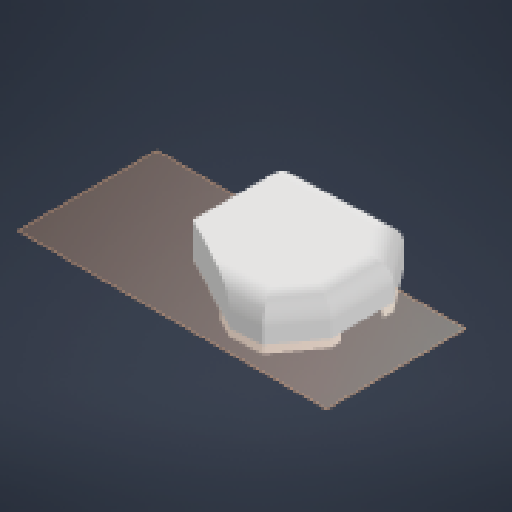
# Autodesk Inventor part: case1
Saved by Autodesk Inventor 2026.2 (Build 302298000, 298)
## iProperties
Created: 2026-10-14
Part Number: case1
Material: Generisch
Document SubType Name: Modeling
Designer: leo
Density: 1 g/cm^3
Appearance: Vorgabe
Author: leo
Autodesk Inventor part; units mm, degrees
ref_plane "YZ Plane" through (0, 0, 0) normal (1, 0, 0) x (0, 1, 0)
ref_plane "XZ Plane" through (0, 0, 0) normal (0, 1, 0) x (-1, 0, 0)
ref_plane "XY Plane" through (0, 0, 0) normal (0, 0, 1) x (1, 0, 0)
ref_plane "Arbeitsebene1" through (0, 0, 0) normal (0, 0, 1) x (1, 0, 0)
sketch "Skizze1" plane through (0, 0, 0) normal (0, 0, 1) x (1, 0, 0)
  line L0 (29.7049, 7.294) -> (29.7049, 3.444) projected
  line L1 (26.9489, 8.327) -> (29.7049, 7.294) projected
  line L2 (20.6569, 8.733) -> (26.9489, 8.327) projected
  line L3 (14.3239, 13.04) -> (20.6569, 8.733) projected
  line L4 (-6.9251, 12.08) -> (14.3239, 13.04) projected
  line L5 (-6.9251, -1.131) -> (-6.9251, 12.08) projected
  line L6 (-26.1451, -1.131) -> (-6.9251, -1.131) projected
  line L7 (-26.8451, -6.991) -> (-26.1451, -1.131) projected
  line L8 (-26.1151, -12.431) -> (-26.8451, -6.991) projected
  line L9 (0.5049, -12.431) -> (-26.1151, -12.431) projected
  line L10 (3.9049, -9.031) -> (0.5049, -12.431) projected
  line L11 (3.9049, -5.536) -> (3.9049, -9.031) projected
  line L12 (8.5589, -2.362) -> (3.9049, -5.536) projected
  line L13 (14.8709, -1.962) -> (8.5589, -2.362) projected
  line L14 (20.7089, 2.008) -> (14.8709, -1.962) projected
  line L15 (26.9489, 2.411) -> (20.7089, 2.008) projected
  line L16 (29.7049, 3.444) -> (26.9489, 2.411) projected
  circle A0 centre (4.6149, -2.071) radius 1.35 projected
  circle A1 centre (1.4409, 9.847) radius 1 projected
  circle A2 centre (1.4409, 3.347) radius 1 projected
  circle A3 centre (-5.0591, 3.347) radius 1 projected
  circle A4 centre (-1.8091, 6.597) radius 0.65 projected
  circle A5 centre (-5.0591, 9.847) radius 1 projected
  line L17 (-6.9251, 19.0871) -> (14.3239, 20.0471)
  line L18 (14.3239, 20.0471) -> (20.6569, 11.733)
  line L19 (20.7089, -0.992) -> (14.8709, -8.962)
  line L20 (20.7089, -0.992) -> (20.6569, 11.733)
  line L21 (14.8709, -8.962) -> (8.5589, -9.362)
  line L22 (-6.9251, 19.0871) -> (-6.9251, -1.131)
  line L23 (8.5589, -9.362) -> (-6.9251, -1.131)
  point P0 (0, 0)
  point P1 (20.6691, 8.7322)
  dimension "d0" = 7
  dimension "d1" = 3
  dimension "d2" = 3
  dimension "d3" = 7
  constraints: 14 end point, 6 vertical alignment, 2 parallel, 1 vertical
  measures "d0" distance between parallel lines of L4 L17
  measures "d1" distance of L2.start L18.end
  measures "d2" distance of L14.start L19.start
  measures "d3" distance of L13.start L19.end
extrude "Extrusion1" add sketch "Skizze1" along normal blind 7 contours L20 L14 L13 L12 L11 L23 L5 L4 L3 L2 | L2 L3 L4 L22 L17 L18 L20 | L20 L19 L21 L23 L11 L12 L13 L14 | A0 | A1 | A2 | A3 | A4 | A5
sketch "Skizze2" plane through (0, 0, 0) normal (0, 0, -1) x (-1, 0, 0)
  line L0 (-29.7049, 7.294) -> (-29.7049, 3.444) projected
  line L1 (-29.7049, 3.444) -> (-26.9489, 2.411) projected
  line L2 (-26.9489, 2.411) -> (-20.7089, 2.008) projected
  line L3 (-20.7089, 2.008) -> (-14.8709, -1.962) projected
  line L4 (-14.8709, -1.962) -> (-8.5589, -2.362) projected
  line L5 (-8.5589, -2.362) -> (-3.9049, -5.536) projected
  line L6 (-3.9049, -5.536) -> (-3.9049, -9.031) projected
  line L7 (-3.9049, -9.031) -> (-0.5049, -12.431) projected
  line L8 (-0.5049, -12.431) -> (26.1151, -12.431) projected
  line L9 (26.1151, -12.431) -> (26.8451, -6.991) projected
  line L10 (26.8451, -6.991) -> (26.1451, -1.131) projected
  line L11 (26.1451, -1.131) -> (6.9251, -1.131) projected
  line L12 (6.9251, -1.131) -> (6.9251, 12.08) projected
  line L13 (6.9251, 12.08) -> (-14.3239, 13.04) projected
  line L14 (-14.3239, 13.04) -> (-20.6569, 8.733) projected
  line L15 (-20.6569, 8.733) -> (-26.9489, 8.327) projected
  line L16 (-26.9489, 8.327) -> (-29.7049, 7.294) projected
  circle A0 centre (-4.6149, -2.071) radius 1.35 projected
  circle A1 centre (-1.4409, 9.847) radius 1 projected
  circle A2 centre (-1.4409, 3.347) radius 1 projected
  circle A3 centre (5.0591, 3.347) radius 1 projected
  circle A4 centre (1.8091, 6.597) radius 0.65 projected
  circle A5 centre (5.0591, 9.847) radius 1 projected
  circle A6 centre (-4.6149, -2.071) radius 2
  circle A7 centre (-1.4409, 9.847) radius 1.5
  circle A8 centre (5.0591, 9.847) radius 1.5
  circle A9 centre (1.8091, 6.597) radius 1
  circle A10 centre (-1.4409, 3.347) radius 1.5
  circle A11 centre (5.0591, 3.347) radius 1.5
  point P0 (0, 0)
  dimension "d6" = 4
  dimension "d7" = 3
  dimension "d8" = 3
  dimension "d9" = 2
  dimension "d10" = 3
  dimension "d11" = 3
  constraints: 6 centre point, 6 coincident
  measures "d6" diameter of A6
  measures "d7" diameter of A7
  measures "d8" diameter of A8
  measures "d9" diameter of A9
  measures "d10" diameter of A10
  measures "d11" diameter of A11
extrude "Extrusion2" cut sketch "Skizze2" against normal blind 4 contours A0 | A1 | A2 | A3 | A4 | A5 | A6 | A7 | A8 | A9 | A10 | A11
sketch "Skizze3" plane through (0, 0, 0) normal (0, 0, -1) x (-1, 0, 0)
  line L0 (-29.7049, 7.294) -> (-29.7049, 3.444) projected
  line L1 (-29.7049, 3.444) -> (-26.9489, 2.411) projected
  line L2 (-26.9489, 2.411) -> (-20.7089, 2.008) projected
  line L3 (-20.7089, 2.008) -> (-14.8709, -1.962) projected
  line L4 (-14.8709, -1.962) -> (-8.5589, -2.362) projected
  line L5 (-8.5589, -2.362) -> (-3.9049, -5.536) projected
  line L6 (-3.9049, -5.536) -> (-3.9049, -9.031) projected
  line L7 (-3.9049, -9.031) -> (-0.5049, -12.431) projected
  line L8 (-0.5049, -12.431) -> (26.1151, -12.431) projected
  line L9 (26.1151, -12.431) -> (26.8451, -6.991) projected
  line L10 (26.8451, -6.991) -> (26.1451, -1.131) projected
  line L11 (26.1451, -1.131) -> (6.9251, -1.131) projected
  line L12 (6.9251, -1.131) -> (6.9251, 12.08) projected
  line L13 (6.9251, 12.08) -> (-14.3239, 13.04) projected
  line L14 (-14.3239, 13.04) -> (-20.6569, 8.733) projected
  line L15 (-20.6569, 8.733) -> (-26.9489, 8.327) projected
  line L16 (-26.9489, 8.327) -> (-29.7049, 7.294) projected
  circle A0 centre (-4.6149, -2.071) radius 1.35 projected
  circle A1 centre (-1.4409, 9.847) radius 1 projected
  circle A2 centre (-1.4409, 3.347) radius 1 projected
  circle A3 centre (5.0591, 3.347) radius 1 projected
  circle A4 centre (1.8091, 6.597) radius 0.65 projected
  circle A5 centre (5.0591, 9.847) radius 1 projected
  line L17 (-14.5249, 13.7498) -> (7.6251, 12.7491)
  line L18 (7.6251, 12.7491) -> (7.6251, -0.431)
  line L19 (7.6251, -0.431) -> (26.7665, -0.431)
  line L20 (26.7665, -0.431) -> (27.5507, -6.9961)
  line L21 (27.5507, -6.9961) -> (26.7275, -13.131)
  line L22 (26.7275, -13.131) -> (-0.7948, -13.131)
  line L23 (-0.7948, -13.131) -> (-4.6049, -9.321)
  line L24 (-4.6049, -9.321) -> (-4.6049, -5.9059)
  line L25 (-4.6049, -5.9059) -> (-8.7947, -3.0485)
  line L26 (-8.7947, -3.0485) -> (-15.1062, -2.6485)
  line L27 (-15.1062, -2.6485) -> (-20.9446, 1.3217)
  line L28 (-20.9446, 1.3217) -> (-27.0974, 1.7191)
  line L29 (-27.0974, 1.7191) -> (-30.4049, 2.9588)
  line L30 (-30.4049, 2.9588) -> (-30.4049, 7.7792)
  line L31 (-30.4049, 7.7792) -> (-27.0974, 9.0188)
  line L32 (-27.0974, 9.0188) -> (-20.8925, 9.4192)
  line L33 (-20.8925, 9.4192) -> (-14.5249, 13.7498)
  circle A6 centre (5.0591, 3.347) radius 1.5 projected
  circle A7 centre (-1.4409, 9.847) radius 1.5 projected
  circle A8 centre (-1.4409, 3.347) radius 1.5 projected
  circle A9 centre (5.0591, 9.847) radius 1.5 projected
  circle A10 centre (1.8091, 6.597) radius 1 projected
  circle A11 centre (-4.6149, -2.071) radius 2 projected
  line L34 (6.9251, 19.0871) -> (6.9251, -1.131) projected
  line L35 (-14.3239, 20.0471) -> (6.9251, 19.0871) projected
  line L36 (-20.6569, 11.733) -> (-14.3239, 20.0471) projected
  line L37 (-20.7089, -0.992) -> (-20.6569, 11.733) projected
  line L38 (-14.8709, -8.962) -> (-20.7089, -0.992) projected
  line L39 (-8.5589, -9.362) -> (-14.8709, -8.962) projected
  line L40 (6.9251, -1.131) -> (-8.5589, -9.362) projected
  point P0 (0, 0)
  point P1 (-20.7001, 1.1555)
  point P2 (-4.6049, -7.2602)
  point P3 (-20.6657, 9.5735)
  point P4 (6.9251, 12.7807)
  dimension "d14" = 0.7
  constraints: 34 end point, 16 other
  measures "d14" distance between parallel lines of L13 L17
extrude "Extrusion3" add sketch "Skizze3" along normal blind 1.6 contours L37 L36 L35 L34 L17 L33 | L27 L26 L25 L24 L40 L39 L38 L37
sketch "Skizze4" plane through (0, 0, -1.6) normal (0, 0, -1) x (-1, 0, 0)
  line L0 (-14.3239, 20.0471) -> (-20.6569, 11.733) projected
  line L1 (-20.6569, 11.733) -> (-20.6657, 9.5735) projected
  line L2 (-20.6657, 9.5735) -> (-14.5249, 13.7498) projected
  line L3 (-14.5249, 13.7498) -> (6.9251, 12.7807) projected
  line L4 (6.9251, 12.7807) -> (6.9251, 19.0871) projected
  line L5 (6.9251, 19.0871) -> (-14.3239, 20.0471) projected
  line L6 (-15.1062, -2.6485) -> (-20.7001, 1.1555) projected
  line L7 (-20.7001, 1.1555) -> (-20.7089, -0.992) projected
  line L8 (-20.7089, -0.992) -> (-14.8709, -8.962) projected
  line L9 (-14.8709, -8.962) -> (-8.5589, -9.362) projected
  line L10 (-8.5589, -9.362) -> (-4.6049, -7.2602) projected
  line L11 (-4.6049, -7.2602) -> (-4.6049, -5.9059) projected
  line L12 (-4.6049, -5.9059) -> (-8.7947, -3.0485) projected
  line L13 (-8.7947, -3.0485) -> (-15.1062, -2.6485) projected
  circle A0 centre (-8.7747, 16.7934) radius 2
  circle A1 centre (1.2253, 16.3416) radius 2
  point P0 (0, 0)
  dimension "d17" = 4
  dimension "d18" = 4
  dimension "d19" = 3.3
  dimension "d20" = 3.3
  dimension "d21" = 10
  constraints: 2 centre point
  measures "d17" diameter of A0
  measures "d18" diameter of A1
  measures "d19" distance from line of L3 A1.centre
  measures "d20" distance from line of L3 A0.centre
  measures "d21" horizontal distance of A1.centre A0.centre
extrude "Extrusion4" cut sketch "Skizze4" against normal blind 4 contours A0 | A1
fillet "Rundung1" radius 4 5 edges at (3.6994, 19.5671, 7) (17.4904, 15.89, 7) (20.6829, 5.3705, 7) (17.7899, -4.977, 7) (11.7149, -9.162, 7)
